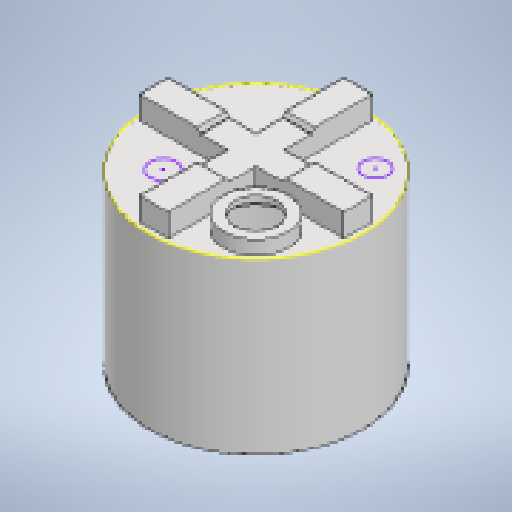
# Autodesk Inventor part: СДР 020 емкость 1500л
Saved by Autodesk Inventor 2025 (Build 290162010, 162A)
## iProperties
Created: 2024-03-31
Part Number: СДР 020 емкость 1500л
Material: Generic
Document SubType Name: Modeling
Designer: admin
Density: 1 g/cm^3
Appearance: Default
Author: admin
Autodesk Inventor part; units mm, degrees
ref_plane "YZ Plane" through (0, 0, 0) normal (1, 0, 0) x (0, 1, 0)
ref_plane "XZ Plane" through (0, 0, 0) normal (0, 1, 0) x (-1, 0, 0)
ref_plane "XY Plane" through (0, 0, 0) normal (0, 0, 1) x (1, 0, 0)
sketch "Sketch1" plane through (0, 0, 0) normal (0, 0, 1) x (1, 0, 0)
  line L0 (0, 0) -> (0, 1185)
  line L1 (0, 1185) -> (750, 1185)
  line L2 (750, 1185) -> (750, 0)
  line L3 (750, 0) -> (0, 0)
  dimension "d0" = 1185
  dimension "d1" = 1500
  constraints: 8 end point, 3 perpendicular, 1 vertical
  measures "d0" distance of L0.start L0.end
  measures "d1" diameter of L2 L0
revolve "Revolution1" add sketch "Sketch1" angle 360 about axis through (0, 0, 0) along (0, 1, 0)
sketch "Sketch2" plane through (0, 1185, 0) normal (0, 1, 0) x (1, 0, 0)
  line L0 (-713.0217, 100) -> (713.0217, 100)
  line L1 (713.0217, 100) -> (713.0217, -100)
  line L2 (713.0217, -100) -> (-713.0217, -100)
  line L3 (-713.0217, -100) -> (-713.0217, 100)
  line L4 (-713.0217, 100) -> (713.0217, -100) construction
  line L5 (713.0217, 100) -> (-713.0217, -100) construction
  line L6 (-100, 713.0217) -> (100, 713.0217)
  line L7 (100, 713.0217) -> (100, -713.0217)
  line L8 (100, -713.0217) -> (-100, -713.0217)
  line L9 (-100, -713.0217) -> (-100, 713.0217)
  line L10 (-100, 713.0217) -> (100, -713.0217) construction
  line L11 (100, 713.0217) -> (-100, -713.0217) construction
  circle A0 centre (0, 0) radius 750 construction
  circle A1 centre (0, 0) radius 720 construction
  point P0 (100, -100)
  point P1 (100, 100)
  point P2 (-100, 100)
  point P3 (-100, -100)
  dimension "d3" = 200
  dimension "d7" = 30
  constraints: 24 end point, 4 midpoint, 4 parallel, 4 perpendicular, 2 horizontal, 3 other
  measures "d3" distance of L6.start L6.end
extrude "Extrusion1" add sketch "Sketch2" along normal blind 160
sketch "Sketch3" plane through (0, 1185, 0) normal (0, 1, 0) x (1, 0, 0)
  circle A0 centre (0, 0) radius 750 construction
  circle A1 centre (353.5534, -353.5534) radius 225
  line L0 (0, 0) -> (530.3301, -530.3301) construction
  line L1 (0, 0) -> (750, 0) construction
  dimension "d8" = 450
  dimension "d9" = 45
  dimension "d10" = 500
  constraints: 4 end point, 2 point on circle, 1 centre point, 1 horizontal, 1 point on line
  measures "d8" diameter of A1
  measures "d9" angle of L0 L1
  measures "d10" distance of point (0, 0) A1.centre
extrude "Extrusion2" add sketch "Sketch3" along normal blind 100
sketch "Sketch4" plane through (0, 1345, 0) normal (0, 1, 0) x (1, 0, 0)
  line L0 (100, -713.0217) -> (100, -100) projected
  line L1 (100, -100) -> (713.0217, -100) projected
  line L2 (713.0217, -100) -> (713.0217, 100) projected
  line L3 (713.0217, 100) -> (100, 100) projected
  line L4 (100, 100) -> (100, 713.0217) projected
  line L5 (100, 713.0217) -> (-100, 713.0217) projected
  line L6 (-100, 713.0217) -> (-100, 100) projected
  line L7 (-100, 100) -> (-713.0217, 100) projected
  line L8 (-713.0217, 100) -> (-713.0217, -100) projected
  line L9 (-713.0217, -100) -> (-100, -100) projected
  line L10 (-100, -100) -> (-100, -713.0217) projected
  line L11 (-100, -713.0217) -> (100, -713.0217) projected
  line L12 (-100, 285) -> (100, 285)
  line L13 (100, 100) -> (713.0217, 100) projected
  line L14 (285, 100) -> (285, -100)
  line L15 (100, -285) -> (-100, -285)
  line L16 (-100, -713.0217) -> (-100, -100) projected
  line L17 (-285, -100) -> (-285, 100)
  line L18 (0, 285) -> (0, -285) construction
  line L19 (285, 0) -> (-285, 0) construction
  point P0 (0, 0)
  point P1 (0, 0)
  dimension "d13" = 570
  dimension "d14" = 570
  constraints: 12 end point, 8 point on line, 6 midpoint, 3 perpendicular, 1 coincident, 1 horizontal
  measures "d13" distance between parallel lines of L15 L12
  measures "d14" distance between parallel lines of L14 L17
extrude "Extrusion3" cut sketch "Sketch4" against normal blind 30 contours L15 L10 L9 L17 L7 L6 L12 L4 L3 L14 L1 L0
chamfer "Chamfer1" distance 25 angle 45 4 edges at (-285, 1345, 0) (0, 1345, -285) (285, 1345, 0) (0, 1345, 285)
sketch "Sketch5" plane through (353.5534, 1285, 353.5534) normal (0, 1, 0) x (1, 0, 0)
  circle A0 centre (0, 0) radius 225 projected
  circle A1 centre (0, 0) radius 150
  point P0 (-353.5534, 353.5534)
  dimension "d20" = 300
  constraints: 1 centre point, 1 coincident
  measures "d20" diameter of A1
extrude "Extrusion4" cut sketch "Sketch5" against normal blind 40 contours A1
shell "Shell1" thickness 4 removed faces 1 at (399.1493, 1245, 378.3762)
sketch "Sketch6" plane through (0, 1185, 0) normal (0, 1, 0) x (1, 0, 0)
  circle A0 centre (0, 0) radius 750 construction
  circle A1 centre (353.5534, 353.5534) radius 12.5
  circle A2 centre (-353.5534, -353.5534) radius 12.5
  line L0 (0, 0) -> (750, 0)
  line L1 (353.5534, 353.5534) -> (-353.5534, -353.5534) construction
  dimension "d24" = 45
  dimension "d25" = 1000
  dimension "d26" = 25
  constraints: 4 end point, 2 centre point, 1 coincident, 1 equal radius, 1 horizontal, 1 horizontal alignment, 1 midpoint, 1 other
  measures "d24" angle of L0 L1
  measures "d25" distance of L1.start L1.end
  measures "d26" diameter of A1
extrude "Extrusion5" add sketch "Sketch6" along normal blind 10
equation "\"d0\" = Tank_H - d5"
equation "\"d1\" = Tank_D"
equation "\"d14\" = d13"
equation "\"Tank_H\" = 1345"
equation "\"Tank_D\" = 1500"
equation "\"d5\" = 160"
body "Solid1"
